main_body_front-v4 (Autodesk Fusion 360 design; units mm, degrees)
part number: main body front
Autodesk Fusion 360 part; units mm, degrees
sketch "main body" plane through (0, 0, 0) normal (0, 1, 0) x (1, 0, 0)
  line L0 (0, 0) -> (249.5, 0)
  line L1 (249.5, 0) -> (249.5, -75.5)
  line L2 (249.5, -75.5) -> (0, -75.5)
  line L3 (0, -75.5) -> (0, 0)
  circle A0 centre (124.75, -18.75) radius 1.1
  circle A1 centre (141.2045, -47.25) radius 1.1
  circle A2 centre (124.75, -37.75) radius 17.75
  circle A3 centre (124.75, -56.75) radius 1.1
  circle A4 centre (108.2955, -47.25) radius 1.1
  circle A5 centre (141.2045, -28.25) radius 1.1
  circle A6 centre (124.75, -37.75) radius 16.25 construction
  circle A7 centre (124.75, -37.75) radius 21
  circle A8 centre (124.75, -37.75) radius 17
  circle A9 centre (108.2955, -28.25) radius 1.1
  line L4 (251.5, -77.5) -> (-2, -77.5)
  line L5 (-2, -77.5) -> (-2, 2)
  line L6 (-2, 2) -> (251.5, 2)
  line L7 (251.5, 2) -> (251.5, -77.5)
  circle A10 centre (32.75, -18.75) radius 1.1
  circle A11 centre (49.2045, -47.25) radius 1.1
  circle A12 centre (32.75, -37.75) radius 17.75
  circle A13 centre (32.75, -56.75) radius 1.1
  circle A14 centre (16.2955, -47.25) radius 1.1
  circle A15 centre (49.2045, -28.25) radius 1.1
  circle A16 centre (32.75, -37.75) radius 16.25 construction
  circle A17 centre (32.75, -37.75) radius 21
  circle A18 centre (32.75, -37.75) radius 17
  circle A19 centre (16.2955, -28.25) radius 1.1
  circle A20 centre (78.75, -18.75) radius 1.1
  circle A21 centre (95.2045, -47.25) radius 1.1
  circle A22 centre (78.75, -37.75) radius 17.75
  circle A23 centre (78.75, -56.75) radius 1.1
  circle A24 centre (62.2955, -47.25) radius 1.1
  circle A25 centre (95.2045, -28.25) radius 1.1
  circle A26 centre (78.75, -37.75) radius 16.25 construction
  circle A27 centre (78.75, -37.75) radius 21
  circle A28 centre (78.75, -37.75) radius 17
  circle A29 centre (62.2955, -28.25) radius 1.1
  circle A30 centre (170.75, -18.75) radius 1.1
  circle A31 centre (187.2045, -47.25) radius 1.1
  circle A32 centre (170.75, -37.75) radius 17.75
  circle A33 centre (170.75, -56.75) radius 1.1
  circle A34 centre (154.2955, -47.25) radius 1.1
  circle A35 centre (187.2045, -28.25) radius 1.1
  circle A36 centre (170.75, -37.75) radius 16.25 construction
  circle A37 centre (170.75, -37.75) radius 21
  circle A38 centre (170.75, -37.75) radius 17
  circle A39 centre (154.2955, -28.25) radius 1.1
  circle A40 centre (216.75, -18.75) radius 1.1
  circle A41 centre (233.2045, -47.25) radius 1.1
  circle A42 centre (216.75, -37.75) radius 17.75
  circle A43 centre (216.75, -56.75) radius 1.1
  circle A44 centre (200.2955, -47.25) radius 1.1
  circle A45 centre (233.2045, -28.25) radius 1.1
  circle A46 centre (216.75, -37.75) radius 16.25 construction
  circle A47 centre (216.75, -37.75) radius 21
  circle A48 centre (216.75, -37.75) radius 17
  circle A49 centre (200.2955, -28.25) radius 1.1
  line L8 (0, -75.5) -> (-2, -75.5)
  line L9 (0, 0) -> (-2, 0)
  line L10 (249.5, 0) -> (251.5, 0)
  line L11 (249.5, -75.5) -> (251.5, -75.5)
  point P0 (124.75, -37.75)
  point P1 (124.75, -75.5)
  point P2 (0, -37.75)
  dimension "d42" = 249.5
  dimension "d43" = 75.5
  dimension "d44" = -0.75
  dimension "d45" = 4
  dimension "d47" = 360
  dimension "d48" = 32.5
  dimension "d49" = 35.5
  dimension "d50" = 2.2
  dimension "d51" = 19
  dimension "d70" = 92
  dimension "d71" = 0
  constraint horizontal L0
  constraint vertical L1
  constraint horizontal L2
  constraint vertical L3
  constraint coincident L0.start L3.end
  constraint coincident P0 A2.centre
  constraint concentric A2 A6
  constraint midpoint L2 P1
  constraint vertical P0 P1
  constraint midpoint L3 P2
  constraint horizontal P0 P2
  constraint coincident L5 L8.end
  constraint perpendicular L5 L8
  constraint coincident L5 L9.end
  constraint perpendicular L5 L9
  constraint coincident L7 L10.end
  constraint perpendicular L7 L10
  constraint coincident L7 L11.end
  constraint perpendicular L7 L11
  measures "d42" distance of L0.start L0.end
  measures "d43" distance of L0.start L2.end
  measures "d48" diameter of A6
  measures "d49" diameter of A2
  measures "d50" diameter of A0
  measures "d51" vertical distance of A0.centre P0
extrude "Extrude1" add sketch "main body" along normal blind 2 contours L0 L5 L6 L7 L9 L10 | L0 L1 L2 L3 | L3 L5 L8 L9 | L1 L7 L10 L11 | L2 L4 L5 L7 L8 L11 | A2 | A7 | A12 | A17 | A22 | A27 | A32 | A37 | A42 | A47
extrude "Extrude2" add sketch "main body" along normal blind 40 contours L0 L5 L6 L7 L9 L10 | L2 L4 L5 L7 L8 L11
fillet "Fillet1" radius 12 2 edges at (124.75, 2, 75.5) (124.75, 2, 0)
fillet "Fillet1" radius 12 2 edges at (124.75, 0, 77.5) (124.75, 0, -2)
equation "disp_actual_displayed_dia = 32.5 mm" comment "actual dia where pixels are shown"
equation "disp_pcb_dia = 38 mm"
equation "disp_substrate_dia = 35.5 mm"
equation "watch_crystal_dia = 35.5 mm"
equation "watch_crystal_thickness = 2 mm"
equation "watch_crystal_center_height = 3.8 mm"
equation "bezel_frame_width = 4 mm"
equation "bezel_thickness = 4 mm"
equation "bezel_rabbet_wall_offset = 0.75 mm"
equation "bezel_pin_length = 4 mm"
equation "bezel_watch_crystal_tolerance = 0.2 mm" comment "extra allowance for fitting of crystal into bezel"
equation "bezel_total_dia = watch_crystal_dia - bezel_rabbet_wall_offset * 2 + bezel_frame_width * 2"
equation "distance_between_disp_holes = bezel_frame_width * 3"
equation "distance_bezel_to_end = bezel_frame_width * 3"
equation "main_body_width = watch_crystal_dia * 5 + distance_between_disp_holes * 4 + distance_bezel_to_end * 2"
equation "distance_bezel_to_top_bottom = 20 mm" comment "minumum is about 20 due to the curve interference w lower display PCB"
equation "main_body_height = watch_crystal_dia + distance_bezel_to_top_bottom * 2"
equation "d42 = main_body_width"
equation "d43 = main_body_height"
equation "d49 = disp_hole_dia"
equation "disp_hole_dia = disp_substrate_dia"
equation "main_body_wall_thickness = 2 mm"
equation "d58 = -main_body_wall_thickness"
equation "d59 = main_body_wall_thickness"
equation "main_body_depth = 40 mm" comment "30mm minimum"
equation "d62 = main_body_depth"
equation "d70 = ( bezel_total_dia * 4 + bezel_frame_width * 4 ) / 2"
